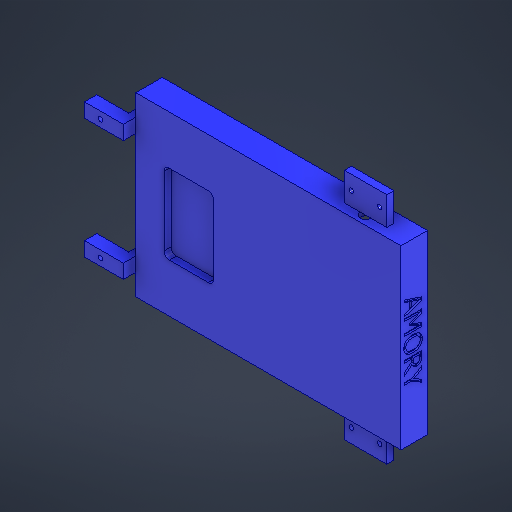
# Autodesk Inventor part: frame
Saved by Autodesk Inventor 2026.1 (Build 301233020, 233B)
## iProperties
Created: 2026-11-09
Part Number: frame
Material: Generic
Document SubType Name: Modeling
Designer: amory
Density: 1 g/cm^3
Appearance: Blue - Wall Paint - Glossy
Author: amory
Autodesk Inventor part; units mm, degrees
ref_plane "YZ Plane" through (0, 0, 0) normal (1, 0, 0) x (0, 1, 0)
ref_plane "XZ Plane" through (0, 0, 0) normal (0, 1, 0) x (-1, 0, 0)
ref_plane "XY Plane" through (0, 0, 0) normal (0, 0, 1) x (1, 0, 0)
sketch "Sketch1" plane through (0, 0, 0) normal (0, 1, 0) x (-1, 0, 0)
  line L0 (0, 0) -> (150, 0)
  line L1 (150, 0) -> (150, -100)
  line L2 (150, -100) -> (0, -100)
  line L3 (0, -100) -> (0, 0)
  dimension "d0" = 150
  dimension "d1" = 100
  constraints: 8 end point, 2 parallel, 1 horizontal, 1 perpendicular
  measures "d0" distance of L1.end L2.end
  measures "d1" distance of L0.end L1.end
extrude "Extrusion1" add sketch "Sketch1" along normal blind 15
sketch "Sketch2" plane through (0, 15, 0) normal (0, 1, 0) x (1, 0, 0)
  line L0 (-56, 22.5) -> (-144, 22.5)
  line L1 (-144, 22.5) -> (-144, 77.5)
  line L2 (-144, 77.5) -> (-56, 77.5)
  line L3 (-56, 77.5) -> (-56, 22.5)
  line L4 (-56, 22.5) -> (-144, 77.5) construction
  line L5 (-144, 22.5) -> (-56, 77.5) construction
  line L6 (0, 0) -> (0, 100) projected
  line L7 (-150, 0) -> (0, 0) projected
  point P0 (-100, 50)
  point P1 (0, 50)
  point P2 (0, 50)
  dimension "d4" = 88
  dimension "d5" = 55
  dimension "d9" = 50
  dimension "d106" = 100
  constraints: 12 end point, 4 midpoint, 2 parallel, 1 horizontal, 1 perpendicular
  measures "d4" distance of L1.end L2.end
  measures "d5" distance of L0.end L1.end
  measures "d9" distance from line of L7 point (-100, 50)
  measures "d106" distance of point (-100, 50) point (0, 50)
extrude "Extrusion2" cut sketch "Sketch2" against normal blind 10
sketch "Sketch4" plane through (-150, 0, 0) normal (0, 0, 1) x (1, 0, 0)
  line L0 (113, 9) -> (137, 9)
  line L1 (137, 9) -> (137, 5)
  line L2 (137, 5) -> (113, 5)
  line L3 (113, 5) -> (113, 9)
  line L4 (113, 9) -> (137, 5) construction
  line L5 (137, 9) -> (113, 5) construction
  line L6 (150, 0) -> (150, 15) projected
  line L7 (0, 15) -> (150, 15) projected
  point P0 (125, 7)
  point P1 (137, 7)
  point P2 (113, 7)
  point P3 (150, 7.5)
  dimension "d16" = 24
  dimension "d17" = 4
  dimension "d18" = 25
  dimension "d19" = 8
  constraints: 12 end point, 5 midpoint, 2 parallel, 1 horizontal, 1 perpendicular
  measures "d16" distance of point (137, 7) point (113, 7)
  measures "d17" distance between parallel lines of L2 L0
  measures "d18" horizontal distance of point (150, 7.5) point (125, 7)
  measures "d19" distance from line of L7 point (125, 7)
extrude "Extrusion4" add sketch "Sketch4" along normal blind 16
sketch "Sketch5" plane through (0, 0, -100) normal (0, 0, -1) x (-1, 0, 0)
  line L0 (13, 5) -> (37, 5)
  line L1 (37, 5) -> (37, 9)
  line L2 (37, 9) -> (13, 9)
  line L3 (13, 9) -> (13, 5)
  line L4 (13, 5) -> (37, 9) construction
  line L5 (37, 5) -> (13, 9) construction
  line L6 (0, 15) -> (150, 15) projected
  line L7 (0, 0) -> (0, 15) projected
  point P0 (25, 7)
  dimension "d22" = 24
  dimension "d23" = 4
  dimension "d24" = 8
  dimension "d25" = 25
  constraints: 12 end point, 2 midpoint, 2 parallel, 1 horizontal, 1 perpendicular
  measures "d22" distance of L2.end L1.end
  measures "d23" distance of L1.end L0.end
  measures "d24" distance from line of L6 point (25, 7)
  measures "d25" distance from line of L7 point (25, 7)
extrude "Extrusion5" add sketch "Sketch5" along normal blind 16
sketch "Sketch6" plane through (-37, 5, -100) normal (0, -1, 0) x (1, 0, 0)
  line L0 (0, 0) -> (0, -16) projected
  line L1 (24, -16) -> (0, -16) projected
  point P0 (37, 100)
  point P1 (20, -8)
  point P2 (4, -8)
  dimension "d28" = 16
  dimension "d29" = 4
  dimension "d30" = 8
  dimension "d31" = 8
  measures "d28" distance of point (4, -8) point (20, -8)
  measures "d29" distance from line of L0 point (4, -8)
  measures "d30" distance from line of L1 point (4, -8)
  measures "d31" distance from line of L1 point (20, -8)
hole "Hole1" at (-17, 5, -108) at (-33, 5, -108) direction (0, 1, 0) diameter 2.5 end through all
sketch "Sketch7" plane through (-37, 9, 0) normal (0, 1, 0) x (1, 0, 0)
  line L0 (24, 0) -> (24, -16) projected
  line L1 (24, -16) -> (0, -16) projected
  line L2 (0, 0) -> (0, -16) projected
  point P0 (37, 0)
  point P1 (20, -8)
  point P2 (4, -8)
  dimension "d39" = 16
  dimension "d41" = 8
  dimension "d42" = 8
  dimension "d43" = 4
  measures "d39" distance of point (4, -8) point (20, -8)
  measures "d41" distance from line of L1 point (20, -8)
  measures "d42" distance from line of L1 point (4, -8)
  measures "d43" distance from line of L2 point (4, -8)
hole "Hole2" at (-17, 9, 8) at (-33, 9, 8) direction (0, -1, 0) diameter 2.5 end through all
sketch "Sketch8" plane through (-150, 0, 0) normal (0, 0, 1) x (1, 0, 0)
  line L0 (113, 5) -> (137, 5) projected
  line L1 (150, 0) -> (150, 15) projected
  point P0 (125, 5)
  point P1 (150, 7.5)
  dimension "d100" = 25
  constraints: 2 midpoint
  measures "d100" horizontal distance of point (150, 7.5) point (125, 5)
hole "Hole3" at (-25, 5, 0) direction (0, 0, -1) diameter 6 depth 5
sketch "Sketch9" plane through (0, 0, -100) normal (0, 0, -1) x (-1, 0, 0)
  line L0 (0, 0) -> (0, 15) projected
  line L1 (0, 0) -> (150, 0) projected
  point P0 (25, 5)
  dimension "d65" = 25
  dimension "d66" = 5
  measures "d65" distance from line of L0 point (25, 5)
  measures "d66" distance from line of L1 point (25, 5)
hole "Hole4" at (-25, 5, -100) direction (0, 0, 1) diameter 6 depth 5
sketch "Sketch10" plane through (-150, 0, -100) normal (-1, 0, 0) x (0, 0, 1)
  line L0 (12, -7) -> (20, -7)
  line L1 (20, -7) -> (20, 13)
  line L2 (20, 13) -> (12, 13)
  line L3 (12, 13) -> (12, -7)
  line L4 (77.5, 5) -> (22.5, 5) projected
  line L5 (12, -7) -> (20, 13) construction
  line L6 (20, -7) -> (12, 13) construction
  line L7 (60, 0) -> (60, 15) projected
  line L8 (0, 0) -> (0, 15) projected
  line L9 (80, -7) -> (88, -7)
  line L10 (88, -7) -> (88, 13)
  line L11 (88, 13) -> (80, 13)
  line L12 (80, 13) -> (80, -7)
  line L13 (80, -7) -> (88, 13) construction
  line L14 (88, -7) -> (80, 13) construction
  line L15 (100, 0) -> (100, 15) projected
  line L16 (0, 0) -> (100, 0) projected
  point P0 (16, 3)
  point P1 (84, 3)
  point P2 (16, -7)
  point P3 (84, -7)
  dimension "d67" = 16
  dimension "d68" = 16
  dimension "d69" = 20
  dimension "d70" = 3
  dimension "d71" = 3
  dimension "d72" = 20
  dimension "d73" = 8
  dimension "d74" = 8
  dimension "d108" = 68
  constraints: 24 end point, 6 midpoint, 4 parallel, 2 horizontal, 2 perpendicular
  measures "d67" distance from line of L8 point (16, 3)
  measures "d68" distance from line of L15 point (84, 3)
  measures "d69" vertical distance of point (16, -7) L2.end
  measures "d70" vertical distance of L15.start point (84, 3)
  measures "d71" distance from line of L16 point (16, 3)
  measures "d72" distance from line of point (84, -7) L11
  measures "d73" distance between parallel lines of L10 L12
  measures "d74" distance between parallel lines of L1 L3
  measures "d108" distance of point (84, -7) point (16, -7)
extrude "Extrusion6" add sketch "Sketch10" along normal blind 4
sketch "Sketch11" plane through (-154, 0, -100) normal (-1, 0, 0) x (0, 0, 1)
  line L0 (100, 0) -> (0, 0) projected
  line L1 (9.0991, 0) -> (20, 0)
  line L2 (100, 0) -> (0, 0) projected
  line L3 (50, 0) -> (78, 0)
  line L4 (20, 0) -> (80, 0) projected
  line L5 (80, 0) -> (88, 0)
  line L6 (88, 0) -> (88, -7)
  line L7 (88, -7) -> (80, -7)
  line L8 (80, -7) -> (80, 0)
  line L9 (12, 13) -> (12, -7) projected
  line L10 (12, 0) -> (20, 0)
  line L11 (20, 0) -> (20, -7)
  line L12 (20, -7) -> (12, -7)
  line L13 (12, -7) -> (12, 0)
  constraints: 20 end point, 4 horizontal, 4 parallel, 3 point on line, 2 perpendicular, 1 midpoint
extrude "Extrusion7" add sketch "Sketch11" along normal blind 18
sketch "Sketch12" plane through (0, 0, 0) normal (0, -1, 0) x (1, 0, 0)
  line L0 (-109, -27.5) -> (-131, -27.5)
  line L1 (-134, -30.5) -> (-134, -69.5)
  line L2 (-131, -72.5) -> (-109, -72.5)
  line L3 (-106, -69.5) -> (-106, -30.5)
  line L4 (-106, -27.5) -> (-134, -72.5) construction
  line L5 (-134, -27.5) -> (-106, -72.5) construction
  arc A0 (-109, -72.5) -> (-106, -69.5) centre (-109, -69.5) ccw
  arc A1 (-134, -69.5) -> (-131, -72.5) centre (-131, -69.5) ccw
  arc A2 (-131, -27.5) -> (-134, -30.5) centre (-131, -30.5) ccw
  arc A3 (-106, -30.5) -> (-109, -27.5) centre (-109, -30.5) ccw
  line L6 (-150, -80) -> (-150, -20) projected
  line L7 (-150, 0) -> (0, 0) projected
  point P0 (-120, -50)
  point P1 (-150, -50)
  dimension "d79" = 28
  dimension "d80" = 45
  dimension "d81" = 3
  dimension "d98" = 30
  dimension "d99" = 50
  constraints: 12 end point, 8 point on circle, 8 point on line, 8 tangent, 4 centre point, 3 equal radius, 3 midpoint, 2 parallel, 1 horizontal, 1 perpendicular
  measures "d79" distance of L5.end L4.end
  measures "d80" distance of L4.end L5.start
  measures "d81" radius of A0
  measures "d98" distance of point (-120, -50) point (-150, -50)
  measures "d99" distance from line of L7 point (-120, -50)
extrude "Extrusion8" cut sketch "Sketch12" against normal blind 4
sketch "Sketch13" plane through (-150, -7, -88) normal (0, -1, 0) x (1, 0, 0)
  line L0 (0, 0) -> (-22, 0) projected
  line L1 (0, 68) -> (-22, 68) projected
  line L2 (-22, 76) -> (-22, 68) projected
  line L3 (-22, 8) -> (-22, 0) projected
  point P0 (150, 88)
  point P1 (-13, 4)
  point P2 (-13, 72)
  point P3 (-11, 68)
  point P4 (-22, 72)
  point P5 (-4, 0)
  dimension "d85" = 4
  dimension "d88" = 4
  dimension "d107" = 9
  dimension "d109" = 9
  constraints: 2 midpoint
  measures "d85" distance from line of L0 point (-13, 4)
  measures "d88" distance from line of L1 point (-13, 72)
  measures "d107" distance of point (-22, 72) point (-13, 72)
  measures "d109" distance from line of L3 point (-13, 4)
hole "Hole5" at (-163, -7, -84) at (-163, -7, -16) direction (0, 1, 0) diameter 2.5 depth 16
sketch "Sketch15" plane through (0, 15, 0) normal (0, 1, 0) x (1, 0, 0)
  line L0 (-6.25, 97.5) -> (-49.75, 97.5)
  line L1 (-49.75, 97.5) -> (-49.75, 2.5)
  line L2 (-49.75, 2.5) -> (-6.25, 2.5)
  line L3 (-6.25, 2.5) -> (-6.25, 97.5)
  line L4 (-6.25, 97.5) -> (-49.75, 2.5) construction
  line L5 (-49.75, 97.5) -> (-6.25, 2.5) construction
  line L6 (-56, 77.5) -> (-56, 22.5) projected
  line L7 (-150, 0) -> (0, 0) projected
  line L8 (0, 0) -> (0, 100) projected
  point P0 (-28, 50)
  point P1 (-56, 50)
  dimension "d103" = 50
  dimension "d104" = 43.5
  dimension "d105" = 95
  dimension "d110" = 28
  constraints: 12 end point, 3 midpoint, 2 parallel, 1 horizontal, 1 perpendicular
  measures "d103" distance from line of L7 point (-28, 50)
  measures "d104" distance between parallel lines of L1 L3
  measures "d105" distance between parallel lines of L0 L2
  measures "d110" distance from line of L8 point (-28, 50)
extrude "Extrusion10" cut sketch "Sketch15" against normal blind 10
sketch "Sketch16" plane through (-56, 15, -77.5) normal (-1, 0, 0) x (0, 0, 1)
  circle A0 centre (7, -6) radius 3
  circle A1 centre (48, -6) radius 3
  line L0 (0, 0) -> (0, -10) projected
  line L1 (55, 0) -> (55, -10) projected
  line L2 (0, -10) -> (55, -10) projected
  point P0 (77.5, -15)
  point P1 (0, -5)
  dimension "d113" = 6
  dimension "d114" = 6
  dimension "d115" = 7
  dimension "d116" = 7
  dimension "d117" = 4
  dimension "d118" = 4
  constraints: 2 centre point, 1 midpoint
  measures "d113" diameter of A0
  measures "d114" diameter of A1
  measures "d115" horizontal distance of point (0, -5) A0.centre
  measures "d116" distance from line of L1 A1.centre
  measures "d117" distance from line of L2 A1.centre
  measures "d118" distance from line of L2 A0.centre
extrude "Extrusion11" cut sketch "Sketch16" against normal blind 10
fillet "Fillet2" radius 2 3 edges at (-28, 5, -3.75) (-22, 5, -3.75) (-25, 5, -5)
fillet "Fillet3" radius 2 3 edges at (-22, 5, -96.25) (-28, 5, -96.25) (-25, 5, -95)
sketch "Sketch17" plane through (0, 0, 0) normal (1, 0, 0) x (0, 0, -1)
  line L0 (27.5812, 12.0136) -> (82.7046, 12.0136) construction
  line L1 (82.7046, 12.0136) -> (82.7046, 2.5735) construction
  line L2 (82.7046, 2.5735) -> (27.5812, 2.5735) construction
  line L3 (27.5812, 2.5735) -> (27.5812, 12.0136) construction
  line L4 (27.5164, 1.8029) -> (30.8876, 11.8029)
  line L5 (30.8876, 11.8029) -> (32.5245, 11.8029)
  line L6 (32.5245, 11.8029) -> (35.8957, 1.8029)
  line L7 (35.8957, 1.8029) -> (34.4937, 1.8029)
  line L8 (34.4937, 1.8029) -> (33.5861, 4.5987)
  line L9 (33.5861, 4.5987) -> (29.7692, 4.5987)
  line L10 (29.7692, 4.5987) -> (28.8616, 1.8029)
  line L11 (28.8616, 1.8029) -> (27.5164, 1.8029)
  line L12 (33.2214, 5.7332) -> (31.6736, 10.4414)
  line L13 (31.6736, 10.4414) -> (30.1339, 5.7332)
  line L14 (30.1339, 5.7332) -> (33.2214, 5.7332)
  line L15 (45.4175, 1.8029) -> (44.0885, 1.8029)
  line L16 (44.0885, 1.8029) -> (44.0885, 10.4171)
  line L17 (44.0885, 10.4171) -> (41.4791, 4.5581)
  line L18 (41.4791, 4.5581) -> (40.6688, 4.5581)
  line L19 (40.6688, 4.5581) -> (38.0837, 10.4171)
  line L20 (38.0837, 10.4171) -> (38.0837, 1.8029)
  line L21 (38.0837, 1.8029) -> (36.8438, 1.8029)
  line L22 (36.8438, 1.8029) -> (36.8438, 11.8029)
  line L23 (36.8438, 11.8029) -> (38.659, 11.8029)
  line L24 (38.659, 11.8029) -> (41.155, 6.2356)
  line L25 (41.155, 6.2356) -> (43.5699, 11.8029)
  line L26 (43.5699, 11.8029) -> (45.4175, 11.8029)
  line L27 (45.4175, 11.8029) -> (45.4175, 1.8029)
  spline S0 degree 2 poles (54.518, 10.6602) (55.0853, 9.9957) (55.7174, 8.0508) (55.7174, 6.8029) knots 0 0 0 1 2 2 2
  spline S1 degree 2 poles (55.7174, 6.8029) (55.7174, 5.5873) (55.1015, 3.6181) (54.518, 2.9536) knots 0 0 0 1 2 2 2
  spline S2 degree 2 poles (54.518, 2.9536) (53.9021, 2.2567) (52.2733, 1.5922) (51.2927, 1.5922) knots 0 0 0 1 2 2 2
  spline S3 degree 2 poles (51.2927, 1.5922) (50.2798, 1.5922) (48.659, 2.281) (48.0675, 2.9536) knots 0 0 0 1 2 2 2
  spline S4 degree 2 poles (48.0675, 2.9536) (47.4921, 3.6181) (46.8762, 5.5711) (46.8762, 6.8029) knots 0 0 0 1 2 2 2
  spline S5 degree 2 poles (46.8762, 6.8029) (46.8762, 8.0589) (47.5002, 9.9714) (48.0756, 10.6602) knots 0 0 0 1 2 2 2
  spline S6 degree 2 poles (48.0756, 10.6602) (48.659, 11.3247) (50.2879, 12.0136) (51.2927, 12.0136) knots 0 0 0 1 2 2 2
  spline S7 degree 2 poles (51.2927, 12.0136) (52.3138, 12.0136) (53.9508, 11.3004) (54.518, 10.6602) knots 0 0 0 1 2 2 2
  spline S8 degree 2 poles (54.3316, 6.8029) (54.3316, 7.7915) (53.9021, 9.3231) (53.5132, 9.8256) knots 0 0 0 1 2 2 2
  spline S9 degree 2 poles (53.5132, 9.8256) (53.1161, 10.3442) (51.9978, 10.8628) (51.3008, 10.8628) knots 0 0 0 1 2 2 2
  spline S10 degree 2 poles (51.3008, 10.8628) (50.5796, 10.8628) (49.4937, 10.3604) (49.0804, 9.8256) knots 0 0 0 1 2 2 2
  spline S11 degree 2 poles (49.0804, 9.8256) (48.6833, 9.315) (48.2619, 7.7753) (48.2619, 6.8029) knots 0 0 0 1 2 2 2
  spline S12 degree 2 poles (48.2619, 6.8029) (48.2619, 4.8337) (49.9151, 2.7429) (51.3008, 2.7429) knots 0 0 0 1 2 2 2
  spline S13 degree 2 poles (51.3008, 2.7429) (52.6866, 2.7429) (54.3316, 4.8337) (54.3316, 6.8029) knots 0 0 0 1 2 2 2
  line L28 (64.9151, 1.8029) -> (63.189, 1.8029)
  line L29 (63.189, 1.8029) -> (60.0286, 5.7818)
  line L30 (60.0286, 5.7818) -> (58.5051, 5.7818)
  line L31 (58.5051, 5.7818) -> (58.5051, 1.8029)
  line L32 (58.5051, 1.8029) -> (57.176, 1.8029)
  line L33 (57.176, 1.8029) -> (57.176, 11.8029)
  line L34 (57.176, 11.8029) -> (59.753, 11.8029)
  spline S14 degree 2 poles (59.753, 11.8029) (60.612, 11.8029) (61.7709, 11.6165) (62.2976, 11.2761) knots 0 0 0 1 2 2 2
  spline S15 degree 2 poles (62.2976, 11.2761) (62.8243, 10.9358) (63.4321, 9.8742) (63.4321, 9.0881) knots 0 0 0 1 2 2 2
  spline S16 degree 2 poles (63.4321, 9.0881) (63.4321, 7.9941) (62.3138, 6.5111) (61.3576, 6.1546) knots 0 0 0 1 2 2 2
  line L35 (61.3576, 6.1546) -> (64.9151, 1.8029)
  spline S17 degree 2 poles (62.0464, 8.9828) (62.0464, 9.4204) (61.7384, 10.093) (61.4143, 10.3118) knots 0 0 0 1 2 2 2
  spline S18 degree 2 poles (61.4143, 10.3118) (61.1307, 10.4982) (60.377, 10.6521) (59.826, 10.6521) knots 0 0 0 1 2 2 2
  line L36 (59.826, 10.6521) -> (58.5051, 10.6521)
  line L37 (58.5051, 10.6521) -> (58.5051, 6.892)
  line L38 (58.5051, 6.892) -> (59.672, 6.892)
  spline S19 degree 2 poles (59.672, 6.892) (60.2474, 6.892) (61.1631, 7.0946) (61.4791, 7.4106) knots 0 0 0 1 2 2 2
  spline S20 degree 2 poles (61.4791, 7.4106) (61.7709, 7.6862) (62.0464, 8.4641) (62.0464, 8.9828) knots 0 0 0 1 2 2 2
  line L39 (72.7109, 11.8029) -> (69.3316, 6.2275)
  line L40 (69.3316, 6.2275) -> (69.3316, 1.8029)
  line L41 (69.3316, 1.8029) -> (68.0026, 1.8029)
  line L42 (68.0026, 1.8029) -> (68.0026, 6.0897)
  line L43 (68.0026, 6.0897) -> (64.6234, 11.8029)
  line L44 (64.6234, 11.8029) -> (66.0982, 11.8029)
  line L45 (66.0982, 11.8029) -> (68.6833, 7.4025)
  line L46 (68.6833, 7.4025) -> (71.3008, 11.8029)
  line L47 (71.3008, 11.8029) -> (72.7109, 11.8029)
  point P0 (0, 0)
  constraints: 2 other
extrude "Extrusion12" cut sketch "Sketch17" against normal blind 1
equation "\"d72\" = d69"
equation "\"d74\" = d73"
equation "\"d88\" = d85"
equation "\"d107\" = d84"
equation "\"d84\" = 9"
body "Solid1"
